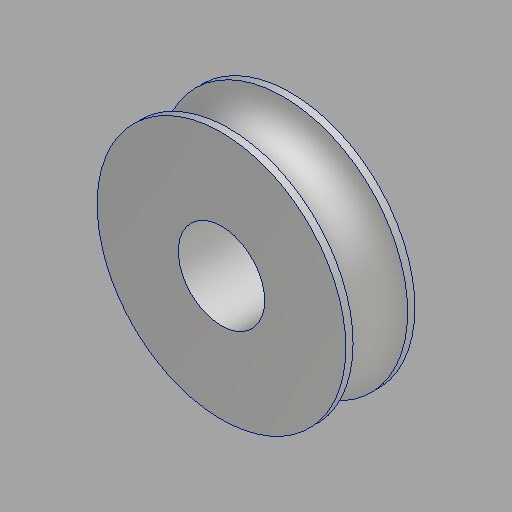
# Autodesk Inventor part: BT009_thutrn22_26
Saved by Autodesk Inventor 2025.3 (Build 293356000, 356)
## iProperties
Company: HTBLA Kaindorf
RuleStatus: InUse
Created: 2026-08-11
Part Number: BT009_thutrn22_26
Project: Biegeroboter
Material: Aluminium 6061
Description: biegerolle_v1
Document SubType Name: Modeling
Designer: thutrn22
Density: 2.7 g/cm^3
Appearance: Aluminium - flach
Mass: 139.059 g
Surface Area: 145.116 cm^2
Volume: 51.5032 cm^3
AfterDocNew0: iProperties-Editor_aufrufen
Author: trist
Keywords: 2026
Autodesk Inventor part; units mm, degrees
ref_plane "YZ Plane" through (0, 0, 0) normal (1, 0, 0) x (0, 1, 0)
ref_plane "XZ Plane" through (0, 0, 0) normal (0, 1, 0) x (-1, 0, 0)
ref_plane "XY Plane" through (0, 0, 0) normal (0, 0, 1) x (1, 0, 0)
sketch "Skizze3" plane through (0, 0, 0) normal (0, 0, 1) x (1, 0, 0)
  line L0 (-4, 0) -> (24, 0) projected
  line L1 (0, -8.78) -> (0, 52.68) projected
  line L2 (0, 10.8665) -> (0, 0)
  line L3 (0, 0) -> (20, 0)
  line L4 (20, 0) -> (20, 36)
  line L5 (20, 36) -> (0, 36)
  line L6 (0, 36) -> (0, 0)
  line L7 (0, 0) -> (20, 0)
  line L8 (20, 0) -> (20, 12.5)
  line L9 (20, 12.5) -> (0, 12.5)
  line L10 (0, 12.5) -> (0, 0)
  line L11 (3, 36) -> (3, 26.7528)
  line L12 (3, 26.7528) -> (0, 26.7528)
  line L13 (17, 36) -> (17, 25.7782)
  line L14 (17, 25.7782) -> (20, 25.7782)
  circle A0 centre (10, 36) radius 7.9
  point P0 (10, 28.1)
  point P1 (2.1, 36)
  point P2 (17.9, 36)
  dimension "d14" = 15.8
  dimension "d5" = 20
  dimension "d6" = 36
  dimension "d7" = 20
  dimension "d8" = 12.5
  dimension "d9" = 3
  dimension "d10" = 3
  dimension "d13" = 28.1
  constraints: 26 end point, 4 parallel, 4 perpendicular, 4 point on line, 2 horizontal, 2 vertical, 1 midpoint, 3 other
  measures "d5" distance of L5.end L4.end
  measures "d6" distance of L4.end L3.end
  measures "d7" distance of L9.end L8.end
  measures "d8" distance of L8.end L7.end
  measures "d9" distance between parallel lines of L6 L11
  measures "d10" distance between parallel lines of L4 L13
  measures "d13" distance from line of L0 point (10, 28.1)
revolve "Umdrehung1" add sketch "Skizze3" angle 360 about axis through (-10, 0, 0) along (1, 0, 0) contours L9 L1 L12 L11 A0 L13 L14 L4 | L14 L13 A0 L5 L4 | L1 L5 A0 L11 L12
